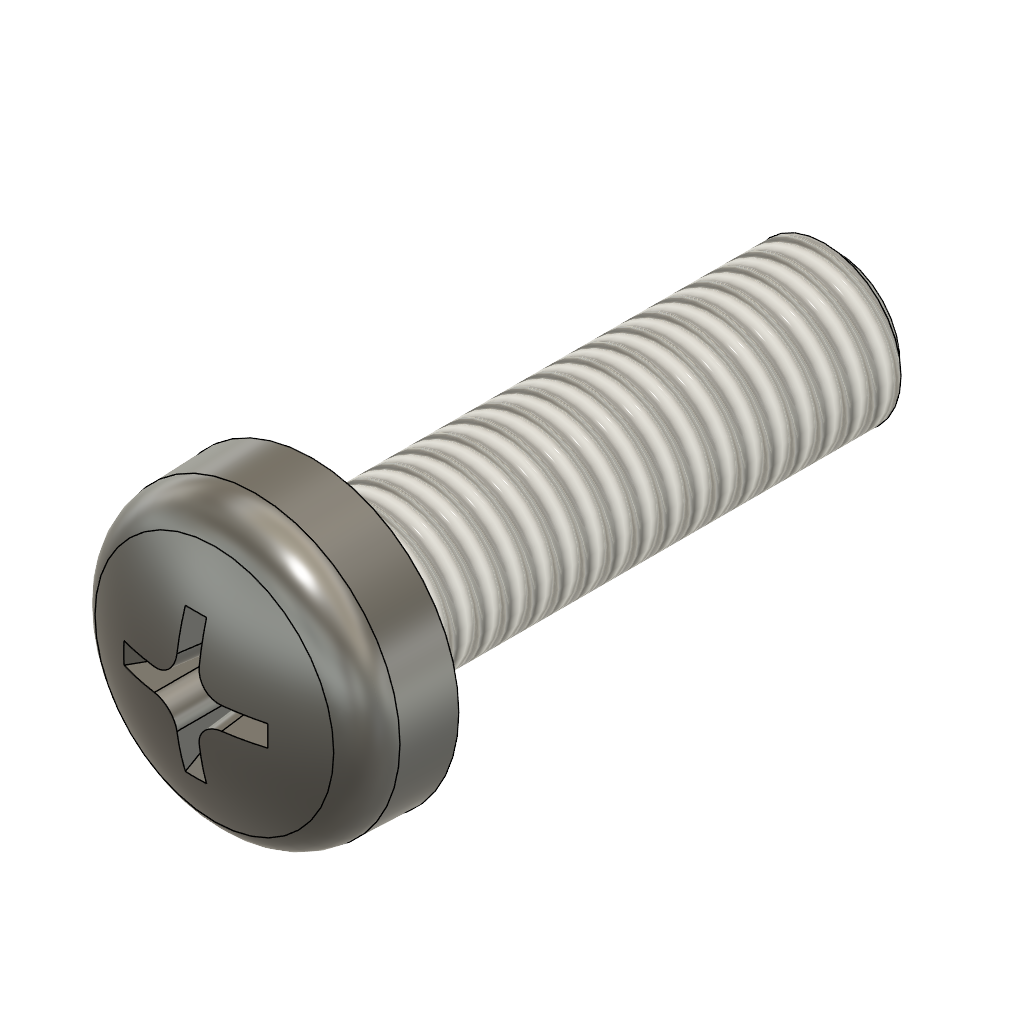
shuffler_assembly (Autodesk Fusion 360 archive; units mm, degrees)
design "Pan Head Screw DIN EN ISO 7045 - M3 x 10 - H Steel 4.6 Plain"
description: Pan Head Screw DIN EN ISO 7045 - M3 x 10 - H
part number: DIN EN ISO 7045 - M3 x 10 - H Steel 4.6 Plain
Autodesk Fusion 360 part; units mm, degrees
sketch "Sketch1" plane through (0, 0, 0) normal (0, 1, 0) x (1, 0, 0)
  line L0 (-1.5, 1) -> (-1.5, 10)
  line L1 (-1.5, 10) -> (0, 10)
  line L2 (0, 10) -> (0, -2.4)
  line L3 (-1.3647, 0) -> (-2.8, 0)
  arc A0 (-2.7449, -1.5792) -> (0, -2.4) centre (0, 2.6) ccw
  line L4 (-1.5, 1) -> (-1.3647, 0.7098)
  line L5 (-1.3647, 0.7098) -> (-1.3647, 0)
  line L6 (-2.8, 0) -> (-2.7449, -1.5792)
  dimension "d9" = 3
  dimension "d66" = 5.6
  dimension "d75" = 2.7294
  dimension "d77" = 1
  dimension "d78" = 155
  dimension "d103" = 2
  dimension "d111" = 2.4
  dimension "d112" = 10
  constraint perpendicular L0 L1
  constraint collinear origin L2.end L1.end
  constraint perpendicular L0 L3
  constraint coincident origin L3
  constraint vertical L0
  constraint vertical L2
  constraint coincident L2 A0.centre
  constraint perpendicular L3 L5
  constraint coincident L3.start L5.end
  measures "d77" distance of L3 L0.start
  measures "d78" angle of L0 L4
  measures "d103" angle of L2 L6
  measures "d111" distance of L2.end L3
  measures "d112" distance of origin L1
revolve "Revolve1" add sketch "Sketch1" angle 360 about axis through (0, 0, -10) along (0, 0, 1) makes body 1
ref_plane "WorkPlane1" through (0, 0, 2.4) normal (0, 0, 1) x (1, 0, 0)
sketch "Sketch2" plane through (0, 0, 2.4) normal (0, 0, 1) x (1, 0, 0)
  line L0 (-0.215, 0.215) -> (-1.5, 0.215)
  line L1 (-0.215, -0.215) -> (-1.5, -0.215)
  line L2 (-1.5, 0.215) -> (-1.5, -0.215)
  line L3 (-0.215, -0.215) -> (-0.215, -1.5)
  line L4 (-0.215, -1.5) -> (0.215, -1.5)
  line L5 (0.215, -0.215) -> (0.215, -1.5)
  line L6 (0.215, -0.215) -> (1.5, -0.215)
  line L7 (1.5, -0.215) -> (1.5, 0.215)
  line L8 (0.215, 0.215) -> (1.5, 0.215)
  line L9 (0.215, 0.215) -> (0.215, 1.5)
  line L10 (0.215, 1.5) -> (-0.215, 1.5)
  line L11 (-0.215, 0.215) -> (-0.215, 1.5)
  dimension "d105" = 0.43
  dimension "d107" = 360
  dimension "d108" = 3
  constraint perpendicular L1 L2
  constraint vertical L0.start L1.start
  constraint horizontal L1
  constraint coincident L8.start L9.start
  measures "d105" distance of L0 L1
  measures "d108" distance of L2 L7
extrude "Extrude1" add sketch "Sketch2" against normal blind 1.8 draft -4 separate body makes body 2
draft "Draft1" angle -30 neutral plane through (0, 0, 2.4) pull (0, 0, 1) 4 faces at (-1.458, -0.0297, 1.8) (0.0297, -1.458, 1.8) (1.458, -0.0297, 1.8) (0.0297, 1.458, 1.8) on bodies 2
fillet "Fillet3" radius 0.43 4 edges at (0.1521, 0.1521, 1.5) (-0.1521, 0.1521, 1.5) (0.1521, -0.1521, 1.5) (-0.1521, -0.1521, 1.5) on bodies 2
combine "Combine1" operation cut target body 1 tool bodies 2
fillet "Fillet4" radius 0.9 1 edges at (-2.5591, 0.9926, 1.5792) on bodies 1
thread "Thread1" "ISO Metric profile 3.0 M3x0.5 M3x0.5 6g" major diameter 2.927 minor diameter 2.3555 pitch 0.5 angle 60 resizes the face on face at (-1.4925, 0.1494, -7) on bodies 1
fillet "Fillet5" radius 0.3 1 edges at (-1.2723, 0.4935, 0) on bodies 1
sketch "Sketch5" plane through (0, 0, 0) normal (0, 1, 0) x (1, 0, 0)
  line L0 (-1.53, 10) -> (-1.53, 9.6933)
  line L1 (-1.53, 9.6933) -> (-1.1933, 10)
  line L2 (0, 10) -> (0, -2.4)
  line L3 (-1.53, 10) -> (0, 10)
  dimension "d114" = 0.3067
  dimension "d115" = 1.53
  dimension "d116" = 0.3367
  constraint coincident L2.start L3.end
  constraint perpendicular L2 L3
  constraint coincident L1.end L3
  constraint perpendicular L0 L3
  measures "d114" distance of L0.end L3
  measures "d115" distance of L0 L2.start
  measures "d116" distance of L0 L1.end
revolve "Revolve2" cut sketch "Sketch5" angle 360 about axis through (0, 0, -10) along (0, 0, 1) bodies 1
equation "d9 = adsk_nomdia"
equation "adsk_nomlen = 10.00 mm"
equation "adsk_headh = 2.40 mm"
equation "adsk_headdia = 5.60 mm"
equation "adsk_nomdia = 3.00 mm"
equation "adsk_phildia = 3.00 mm"
equation "d31 = -adsk_phildepth"
equation "adsk_philwidth = 0.43 mm"
equation "adsk_phildepth = 1.80 mm"
equation "d66 = adsk_headdia"
equation "d71 = adsk_headh"
equation "adsk_thrlen = 9.00 mm"
equation "d75 = adsk_shnkdia"
equation "adsk_shnkdia = 2.72937 mm"
equation "d77 = adsk_nomlen - adsk_thrlen"
equation "adsk_endpointdia = 2.38655 mm"
equation "adsk_startlen = 0.306725 mm"
equation "adsk_ovalrad = 5.00 mm"
equation "adsk_headtoprad = adsk_nomdia * 0.3"
equation "adsk_midfillet = adsk_nomdia * 0.1"
equation "d98 = adsk_midfillet"
equation "adsk_headang = 2.00 deg"
equation "d102 = adsk_headtoprad"
equation "d103 = adsk_headang"
equation "d105 = adsk_philwidth"
equation "d108 = adsk_phildia"
equation "d110 = adsk_philwidth"
equation "d111 = adsk_headh"
equation "d112 = adsk_nomlen"
equation "d113 = ( adsk_nomlen + adsk_headh ) - ( adsk_ovalrad )"
equation "d114 = adsk_startlen"
equation "d115 = adsk_nomdia * 0.51"
equation "d116 = ( adsk_nomdia * 0.51 ) - ( adsk_endpointdia / 2 )"

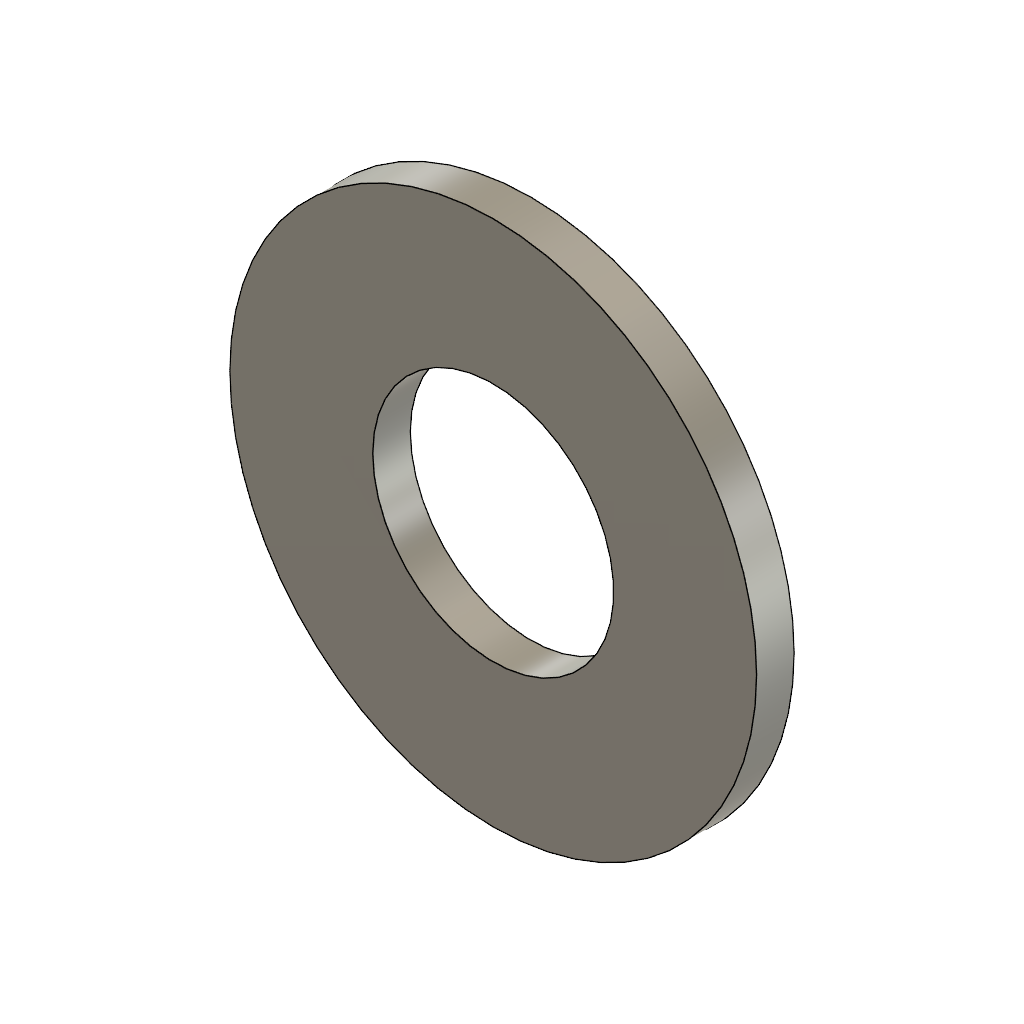
design "Washer ISO 7089 - 3 Steel 100 HV Plain"
description: Washer ISO 7089 - 3
part number: ISO 7089 - 3 Steel 100 HV Plain
Autodesk Fusion 360 part; units mm, degrees
sketch "Sketch1" plane through (0, 0, 0) normal (0, 0, 1) x (1, 0, 0)
  circle A0 centre (0, 0) radius 3.5
  circle A1 centre (0, 0) radius 1.6
  dimension "d4" = 7
  dimension "d5" = 3.2
  constraint coincident A0.centre A1.centre
  measures "d4" diameter of A0
  measures "d5" diameter of A1
extrude "Extrude1" add sketch "Sketch1" along normal blind 0.5
equation "adsk_woutdia = 7.00 mm"
equation "adsk_windia = 3.20 mm"
equation "adsk_wthick = 0.50 mm"
equation "d4 = adsk_woutdia"
equation "d5 = adsk_windia"
equation "d6 = adsk_wthick"
equation "d30 = adsk_wthick"

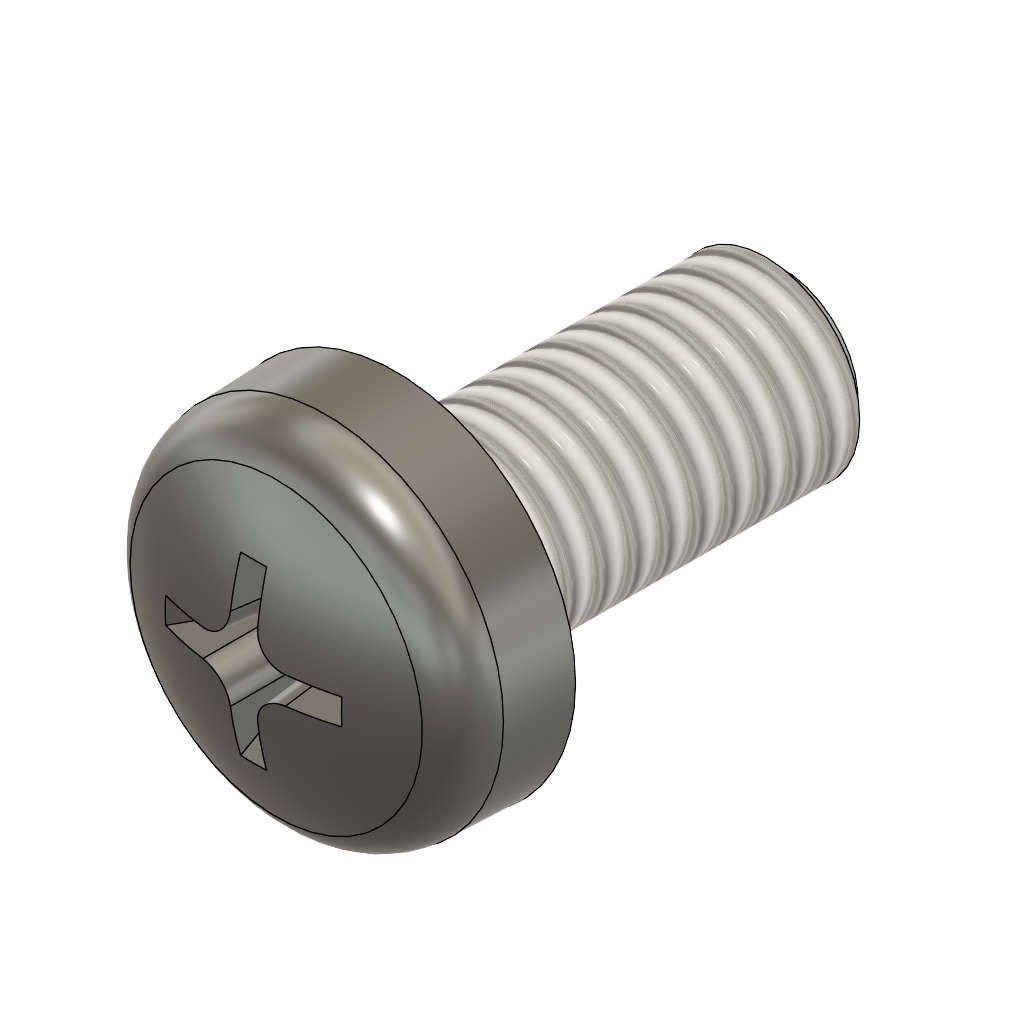
design "Pan Head Screw DIN EN ISO 7045 - M3 x 6 - H Steel 4.6 Plain"
description: Pan Head Screw DIN EN ISO 7045 - M3 x 6 - H
part number: DIN EN ISO 7045 - M3 x 6 - H Steel 4.6 Plain
Autodesk Fusion 360 part; units mm, degrees
sketch "Sketch1" plane through (0, 0, 0) normal (0, 1, 0) x (1, 0, 0)
  line L0 (-1.5, 1) -> (-1.5, 6)
  line L1 (-1.5, 6) -> (0, 6)
  line L2 (0, 6) -> (0, -2.4)
  line L3 (-1.3647, 0) -> (-2.8, 0)
  arc A0 (-2.7449, -1.5792) -> (0, -2.4) centre (0, 2.6) ccw
  line L4 (-1.5, 1) -> (-1.3647, 0.7098)
  line L5 (-1.3647, 0.7098) -> (-1.3647, 0)
  line L6 (-2.8, 0) -> (-2.7449, -1.5792)
  dimension "d9" = 3
  dimension "d66" = 5.6
  dimension "d75" = 2.7294
  dimension "d77" = 1
  dimension "d78" = 155
  dimension "d103" = 2
  dimension "d111" = 2.4
  dimension "d112" = 6
  constraint perpendicular L0 L1
  constraint collinear origin L2.end L1.end
  constraint perpendicular L0 L3
  constraint coincident origin L3
  constraint vertical L0
  constraint vertical L2
  constraint coincident L2 A0.centre
  constraint perpendicular L3 L5
  constraint coincident L3.start L5.end
  measures "d77" distance of L3 L0.start
  measures "d78" angle of L0 L4
  measures "d103" angle of L2 L6
  measures "d111" distance of L2.end L3
  measures "d112" distance of origin L1
revolve "Revolve1" add sketch "Sketch1" angle 360 about axis through (0, 0, -6) along (0, 0, 1) makes body 1
ref_plane "WorkPlane1" through (0, 0, 2.4) normal (0, 0, 1) x (1, 0, 0)
sketch "Sketch2" plane through (0, 0, 2.4) normal (0, 0, 1) x (1, 0, 0)
  line L0 (-0.215, 0.215) -> (-1.5, 0.215)
  line L1 (-0.215, -0.215) -> (-1.5, -0.215)
  line L2 (-1.5, 0.215) -> (-1.5, -0.215)
  line L3 (-0.215, -0.215) -> (-0.215, -1.5)
  line L4 (-0.215, -1.5) -> (0.215, -1.5)
  line L5 (0.215, -0.215) -> (0.215, -1.5)
  line L6 (0.215, -0.215) -> (1.5, -0.215)
  line L7 (1.5, -0.215) -> (1.5, 0.215)
  line L8 (0.215, 0.215) -> (1.5, 0.215)
  line L9 (0.215, 0.215) -> (0.215, 1.5)
  line L10 (0.215, 1.5) -> (-0.215, 1.5)
  line L11 (-0.215, 0.215) -> (-0.215, 1.5)
  dimension "d105" = 0.43
  dimension "d107" = 360
  dimension "d108" = 3
  constraint perpendicular L1 L2
  constraint vertical L0.start L1.start
  constraint horizontal L1
  constraint coincident L8.start L9.start
  measures "d105" distance of L0 L1
  measures "d108" distance of L2 L7
extrude "Extrude1" add sketch "Sketch2" against normal blind 1.8 draft -4 separate body makes body 2
draft "Draft1" angle -30 neutral plane through (0, 0, 2.4) pull (0, 0, 1) 4 faces at (-1.458, -0.0297, 1.8) (0.0297, -1.458, 1.8) (1.458, -0.0297, 1.8) (0.0297, 1.458, 1.8) on bodies 2
fillet "Fillet3" radius 0.43 4 edges at (0.1521, 0.1521, 1.5) (-0.1521, 0.1521, 1.5) (0.1521, -0.1521, 1.5) (-0.1521, -0.1521, 1.5) on bodies 2
combine "Combine1" operation cut target body 1 tool bodies 2
fillet "Fillet4" radius 0.9 1 edges at (-2.5591, 0.9926, 1.5792) on bodies 1
thread "Thread1" "ISO Metric profile 3.0 M3x0.5 M3x0.5 6g" major diameter 2.927 minor diameter 2.3555 pitch 0.5 angle 60 resizes the face on face at (-1.4925, 0.1494, -2.6667) on bodies 1
fillet "Fillet5" radius 0.3 1 edges at (-1.2723, 0.4935, 0) on bodies 1
sketch "Sketch5" plane through (0, 0, 0) normal (0, 1, 0) x (1, 0, 0)
  line L0 (-1.53, 6) -> (-1.53, 5.6933)
  line L1 (-1.53, 5.6933) -> (-1.1933, 6)
  line L2 (0, 6) -> (0, -2.4)
  line L3 (-1.53, 6) -> (0, 6)
  dimension "d114" = 0.3067
  dimension "d115" = 1.53
  dimension "d116" = 0.3367
  constraint coincident L2.start L3.end
  constraint perpendicular L2 L3
  constraint coincident L1.end L3
  constraint perpendicular L0 L3
  measures "d114" distance of L0.end L3
  measures "d115" distance of L0 L2.start
  measures "d116" distance of L0 L1.end
revolve "Revolve2" cut sketch "Sketch5" angle 360 about axis through (0, 0, -6) along (0, 0, 1) bodies 1
equation "d9 = adsk_nomdia"
equation "adsk_nomlen = 6.00 mm"
equation "adsk_headh = 2.40 mm"
equation "adsk_headdia = 5.60 mm"
equation "adsk_nomdia = 3.00 mm"
equation "adsk_phildia = 3.00 mm"
equation "d31 = -adsk_phildepth"
equation "adsk_philwidth = 0.43 mm"
equation "adsk_phildepth = 1.80 mm"
equation "d66 = adsk_headdia"
equation "d71 = adsk_headh"
equation "adsk_thrlen = 5.00 mm"
equation "d75 = adsk_shnkdia"
equation "adsk_shnkdia = 2.72937 mm"
equation "d77 = adsk_nomlen - adsk_thrlen"
equation "adsk_endpointdia = 2.38655 mm"
equation "adsk_startlen = 0.306725 mm"
equation "adsk_ovalrad = 5.00 mm"
equation "adsk_headtoprad = adsk_nomdia * 0.3"
equation "adsk_midfillet = adsk_nomdia * 0.1"
equation "d98 = adsk_midfillet"
equation "adsk_headang = 2.00 deg"
equation "d102 = adsk_headtoprad"
equation "d103 = adsk_headang"
equation "d105 = adsk_philwidth"
equation "d108 = adsk_phildia"
equation "d110 = adsk_philwidth"
equation "d111 = adsk_headh"
equation "d112 = adsk_nomlen"
equation "d113 = ( adsk_nomlen + adsk_headh ) - ( adsk_ovalrad )"
equation "d114 = adsk_startlen"
equation "d115 = adsk_nomdia * 0.51"
equation "d116 = ( adsk_nomdia * 0.51 ) - ( adsk_endpointdia / 2 )"

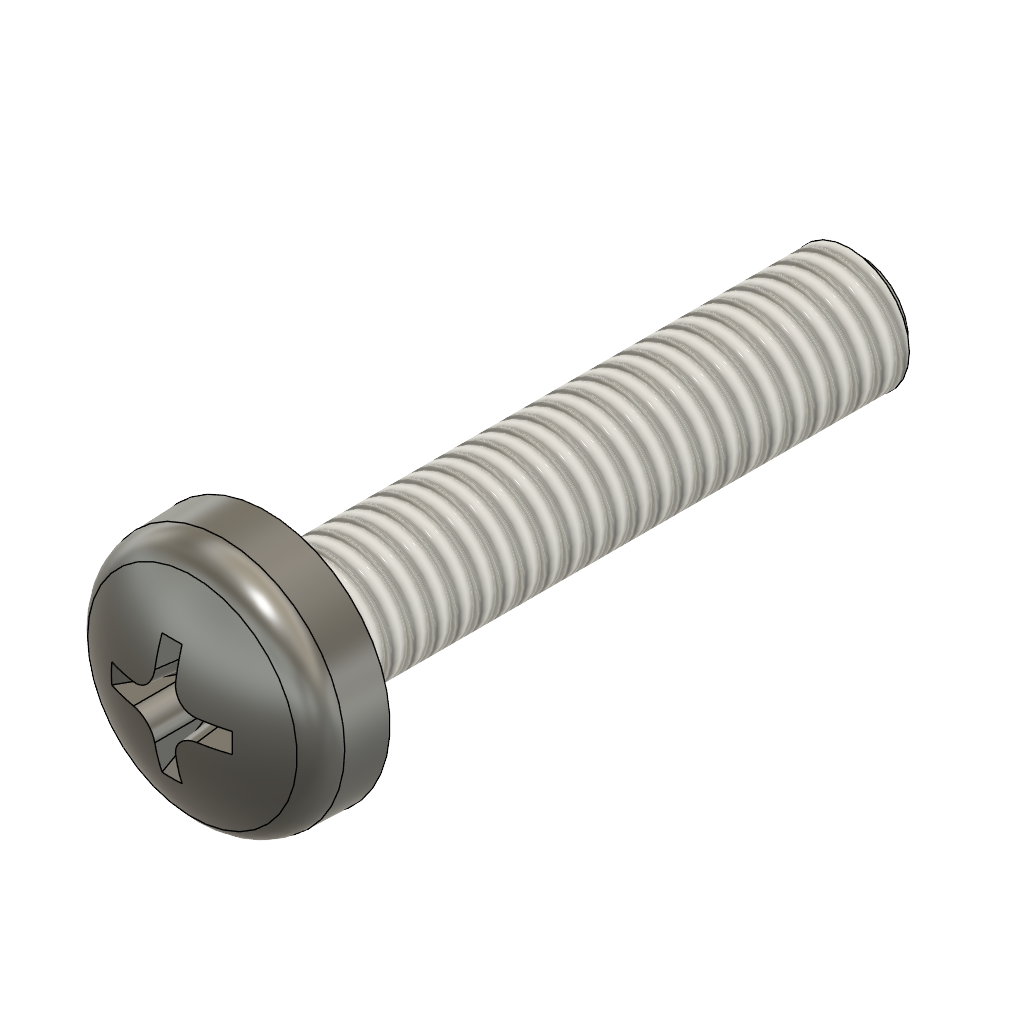
design "Pan Head Screw DIN EN ISO 7045 - M2.5 x 12 - H Steel 4.6 Plain"
description: Pan Head Screw DIN EN ISO 7045 - M2.5 x 12 - H
part number: DIN EN ISO 7045 - M2.5 x 12 - H Steel 4.6 Plain
Autodesk Fusion 360 part; units mm, degrees
sketch "Sketch1" plane through (0, 0, 0) normal (0, 1, 0) x (1, 0, 0)
  line L0 (-1.25, 0.9) -> (-1.25, 12)
  line L1 (-1.25, 12) -> (0, 12)
  line L2 (0, 12) -> (0, -2.1)
  line L3 (-1.1282, 0) -> (-2.5, 0)
  arc A0 (-2.4561, -1.2571) -> (0, -2.1) centre (0, 1.9) ccw
  line L4 (-1.25, 0.9) -> (-1.1282, 0.6388)
  line L5 (-1.1282, 0.6388) -> (-1.1282, 0)
  line L6 (-2.5, 0) -> (-2.4561, -1.2571)
  dimension "d9" = 2.5
  dimension "d66" = 5
  dimension "d75" = 2.2564
  dimension "d77" = 0.9
  dimension "d78" = 155
  dimension "d103" = 2
  dimension "d111" = 2.1
  dimension "d112" = 12
  constraint perpendicular L0 L1
  constraint collinear origin L2.end L1.end
  constraint perpendicular L0 L3
  constraint coincident origin L3
  constraint vertical L0
  constraint vertical L2
  constraint coincident L2 A0.centre
  constraint perpendicular L3 L5
  constraint coincident L3.start L5.end
  measures "d77" distance of L3 L0.start
  measures "d78" angle of L0 L4
  measures "d103" angle of L2 L6
  measures "d111" distance of L2.end L3
  measures "d112" distance of origin L1
revolve "Revolve1" add sketch "Sketch1" angle 360 about axis through (0, 0, -12) along (0, 0, 1) makes body 1
ref_plane "WorkPlane1" through (0, 0, 2.1) normal (0, 0, 1) x (1, 0, 0)
sketch "Sketch2" plane through (0, 0, 2.1) normal (0, 0, 1) x (1, 0, 0)
  line L0 (-0.215, 0.215) -> (-1.35, 0.215)
  line L1 (-0.215, -0.215) -> (-1.35, -0.215)
  line L2 (-1.35, 0.215) -> (-1.35, -0.215)
  line L3 (-0.215, -0.215) -> (-0.215, -1.35)
  line L4 (-0.215, -1.35) -> (0.215, -1.35)
  line L5 (0.215, -0.215) -> (0.215, -1.35)
  line L6 (0.215, -0.215) -> (1.35, -0.215)
  line L7 (1.35, -0.215) -> (1.35, 0.215)
  line L8 (0.215, 0.215) -> (1.35, 0.215)
  line L9 (0.215, 0.215) -> (0.215, 1.35)
  line L10 (0.215, 1.35) -> (-0.215, 1.35)
  line L11 (-0.215, 0.215) -> (-0.215, 1.35)
  dimension "d105" = 0.43
  dimension "d107" = 360
  dimension "d108" = 2.7
  constraint perpendicular L1 L2
  constraint vertical L0.start L1.start
  constraint horizontal L1
  constraint coincident L8.start L9.start
  measures "d105" distance of L0 L1
  measures "d108" distance of L2 L7
extrude "Extrude1" add sketch "Sketch2" against normal blind 1.55 draft -4 separate body makes body 2
draft "Draft1" angle -30 neutral plane through (0, 0, 2.1) pull (0, 0, 1) 4 faces at (-1.3139, 0.0355, 1.5833) (-0.0355, -1.3139, 1.5833) (1.3139, -0.0355, 1.5833) (0.0355, 1.3139, 1.5833) on bodies 2
fillet "Fillet3" radius 0.43 4 edges at (0.1608, 0.1608, 1.325) (-0.1608, 0.1608, 1.325) (0.1608, -0.1608, 1.325) (-0.1608, -0.1608, 1.325) on bodies 2
combine "Combine1" operation cut target body 1 tool bodies 2
fillet "Fillet4" radius 0.75 1 edges at (-2.2899, 0.8882, 1.2571) on bodies 1
thread "Thread1" "ISO Metric profile 2.5 M2.5x0.45 M2.5x0.45 6g" major diameter 2.43 minor diameter 1.9165 pitch 0.45 angle 60 resizes the face on face at (-1.2438, 0.1245, -8.3) on bodies 1
fillet "Fillet5" radius 0.25 1 edges at (-1.0519, 0.408, 0) on bodies 1
sketch "Sketch5" plane through (0, 0, 0) normal (0, 1, 0) x (1, 0, 0)
  line L0 (-1.275, 12) -> (-1.275, 11.7239)
  line L1 (-1.275, 11.7239) -> (-0.9739, 12)
  line L2 (0, 12) -> (0, -2.1)
  line L3 (-1.275, 12) -> (0, 12)
  dimension "d114" = 0.2761
  dimension "d115" = 1.275
  dimension "d116" = 0.3011
  constraint coincident L2.start L3.end
  constraint perpendicular L2 L3
  constraint coincident L1.end L3
  constraint perpendicular L0 L3
  measures "d114" distance of L0.end L3
  measures "d115" distance of L0 L2.start
  measures "d116" distance of L0 L1.end
revolve "Revolve2" cut sketch "Sketch5" angle 360 about axis through (0, 0, -12) along (0, 0, 1) bodies 1
equation "d9 = adsk_nomdia"
equation "adsk_nomlen = 12.00 mm"
equation "adsk_headh = 2.10 mm"
equation "adsk_headdia = 5.00 mm"
equation "adsk_nomdia = 2.50 mm"
equation "adsk_phildia = 2.70 mm"
equation "d31 = -adsk_phildepth"
equation "adsk_philwidth = 0.43 mm"
equation "adsk_phildepth = 1.55 mm"
equation "d66 = adsk_headdia"
equation "d71 = adsk_headh"
equation "adsk_thrlen = 11.10 mm"
equation "d75 = adsk_shnkdia"
equation "adsk_shnkdia = 2.25643 mm"
equation "d77 = adsk_nomlen - adsk_thrlen"
equation "adsk_endpointdia = 1.947895 mm"
equation "adsk_startlen = 0.276053 mm"
equation "adsk_ovalrad = 4.00 mm"
equation "adsk_headtoprad = adsk_nomdia * 0.3"
equation "adsk_midfillet = adsk_nomdia * 0.1"
equation "d98 = adsk_midfillet"
equation "adsk_headang = 2.00 deg"
equation "d102 = adsk_headtoprad"
equation "d103 = adsk_headang"
equation "d105 = adsk_philwidth"
equation "d108 = adsk_phildia"
equation "d110 = adsk_philwidth"
equation "d111 = adsk_headh"
equation "d112 = adsk_nomlen"
equation "d113 = ( adsk_nomlen + adsk_headh ) - ( adsk_ovalrad )"
equation "d114 = adsk_startlen"
equation "d115 = adsk_nomdia * 0.51"
equation "d116 = ( adsk_nomdia * 0.51 ) - ( adsk_endpointdia / 2 )"
